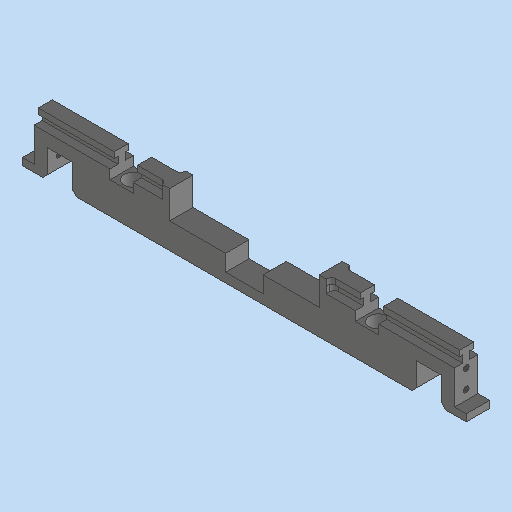
# Autodesk Inventor part: MM0937AN100_G16_152
Saved by Autodesk Inventor 2023.3 (Build 273359000, 359)
## iProperties
Created: 2024-03-13
Part Number: MM0937AN100_G16_152
Material: 1.2379 X155CrVMo12-1
Description: =<RBPARTNOTITLE2>
Document SubType Name: Modeling
Designer: FSM9BW
Mass: 187.923 g
Surface Area: 123.491 cm^2
Volume: 23.9392 cm^3
Density: 7.85 g/cm^3
Appearance: Stahl - rostfrei AnP
RBPARTMADEOF: 23 x 10 x 190 (FM)
RBDRAWINGMISSINGSPEC: --
AnP_Kategorie: 1
RBPARTNOTITLE2: Anfertigungsteil
RBSURFACE: plasma nitrided 1000 HV, Nht 0,1 + 0,1
RBPARTNOTITLE1: manufactured part
RBSURFACE2: plasmanitriert 1000 HV, Nht 0,1 + 0,1
AnP_Material: =<Material>
RBMATERIAL: =<Material>
RBMATNO: =<Part Number>
RBPARTNO: SIEHE MNR
MaxAbmaße: 23 x 10 x 190 (FM)
Author: FSM9BW
Keywords: =<RBPARTMADEOF>
Comments: =<RBSURFACE2>
Revision Number: 01
Autodesk Inventor part; units mm, degrees
ref_plane "YZ Plane" through (0, 0, 0) normal (1, 0, 0) x (0, 1, 0)
ref_plane "XZ Plane" through (0, 0, 0) normal (0, 1, 0) x (-1, 0, 0)
ref_plane "XY Plane" through (0, 0, 0) normal (0, 0, 1) x (1, 0, 0)
sketch "Skizze1" plane through (0, 0, 0) normal (0, 0, 1) x (1, 0, 0)
  line L0 (-95, -5) -> (95, -5)
  line L1 (95, -5) -> (95, 5)
  line L2 (95, 5) -> (-95, 5)
  line L3 (-95, 5) -> (-95, -5)
  line L4 (0, -7) -> (0, 7) projected
  point P0 (0, 0)
  dimension "d0" = 190
  dimension "d1" = 10
  dimension "d2" = 5
  constraints: 8 end point, 2 parallel, 1 horizontal, 1 perpendicular, 1 other
  measures "d0" distance of L1.end L2.end
  measures "d1" distance of L2.end L0.start
  measures "d2" distance from line of L2 point (0, 0)
extrude "Extrusion1" add sketch "Skizze1" along normal blind 23
sketch "Skizze2" plane through (-95, -5, 0) normal (0, -1, 0) x (1, 0, 0)
  line L0 (0, 0) -> (190, 0) projected
  line L1 (190, 0) -> (190, 23) projected
  line L2 (0, 23) -> (190, 23) projected
  line L3 (0, 0) -> (0, 23) projected
  line L4 (63, 23) -> (87, 23)
  line L5 (87, 23) -> (87, 11)
  line L6 (87, 11) -> (63, 11)
  line L7 (63, 11) -> (63, 23)
  line L8 (103, 23) -> (127, 23)
  line L9 (127, 23) -> (127, 11)
  line L10 (127, 11) -> (103, 11)
  line L11 (103, 11) -> (103, 23)
  line L12 (87, 11) -> (103, 11)
  line L13 (103, 11) -> (103, 4)
  line L14 (103, 4) -> (87, 4)
  line L15 (87, 4) -> (87, 11)
  line L16 (0, 0) -> (190, 0) projected
  point P0 (95, 0)
  point P1 (95, 0)
  point P2 (95, 0)
  point P3 (95, 0)
  dimension "d5" = 16
  dimension "d6" = 8
  dimension "d7" = 32
  dimension "d8" = 32
  dimension "d9" = 12
  dimension "d10" = 4
  constraints: 24 end point, 6 parallel, 4 point on line, 3 horizontal, 3 midpoint, 3 perpendicular
  measures "d5" distance between parallel lines of L13 L15
  measures "d6" distance from line of L15 point (95, 0)
  measures "d7" distance from line of L7 point (95, 0)
  measures "d8" distance from line of L9 point (95, 0)
  measures "d9" distance between parallel lines of L2 L6
  measures "d10" distance between parallel lines of L0 L14
extrude "Extrusion2" cut sketch "Skizze2" against normal through all contours L2 L5 L6 L7 | L9 L10 L11 L2 | L2 L11 L12 L5 | L12 L13 L14 L15
sketch "Skizze3" plane through (-95, -5, 0) normal (0, -1, 0) x (1, 0, 0)
  line L0 (63, 11) -> (63, 23) projected
  line L1 (0, 23) -> (63, 23) projected
  line L2 (0, 0) -> (0, 23) projected
  line L3 (0, 0) -> (190, 0) projected
  line L4 (190, 0) -> (190, 23) projected
  line L5 (127, 23) -> (190, 23) projected
  line L6 (127, 23) -> (127, 11) projected
  line L7 (127, 11) -> (103, 11) projected
  line L8 (103, 11) -> (103, 4) projected
  line L9 (103, 4) -> (87, 4) projected
  line L10 (87, 4) -> (87, 11) projected
  line L11 (87, 11) -> (63, 11) projected
  line L12 (0, 3) -> (5, 3)
  line L13 (5, 3) -> (5, 23)
  line L14 (5, 23) -> (0, 23)
  line L15 (0, 23) -> (0, 3)
  line L16 (190, 3) -> (185, 3)
  line L17 (185, 3) -> (185, 23)
  line L18 (185, 23) -> (190, 23)
  line L19 (190, 23) -> (190, 3)
  line L20 (0, 23) -> (63, 23) projected
  point P0 (95, 0)
  dimension "d13" = 5
  dimension "d14" = 20
  dimension "d15" = 5
  dimension "d16" = 20
  constraints: 16 end point, 4 parallel, 3 point on line, 2 horizontal, 2 perpendicular, 1 collinear
  measures "d13" distance of L14.end L13.end
  measures "d14" distance of L13.end L12.end
  measures "d15" distance of L17.end L18.end
  measures "d16" distance of L16.end L17.end
extrude "Extrusion3" cut sketch "Skizze3" against normal through all contours L13 L12 L2 L1 | L16 L17 L5 L4
sketch "Skizze4" plane through (-90, -5, 3) normal (-1, 0, 0) x (0, 0, 1)
  line L0 (0, 10) -> (20, 10) projected
  line L1 (0, 0) -> (0, 10) projected
  line L2 (20, 0) -> (0, 0) projected
  line L3 (20, 10) -> (20, 0) projected
  line L4 (20, 10) -> (20, 7.8)
  line L5 (20, 7.8) -> (17.5, 7.8)
  line L6 (17.5, 7.8) -> (17.5, 6.5)
  line L7 (17.5, 6.5) -> (14.5, 6.5)
  line L8 (14.5, 6.5) -> (14.5, 10)
  line L9 (14.5, 10) -> (20, 10)
  line L10 (20, 1.8) -> (20, 0)
  line L11 (20, 0) -> (14.5, 0)
  line L12 (14.5, 0) -> (14.5, 3.5)
  line L13 (14.5, 3.5) -> (17.5, 3.5)
  line L14 (17.5, 3.5) -> (17.5, 1.8)
  line L15 (17.5, 1.8) -> (20, 1.8)
  point P0 (-3, 5)
  dimension "d19" = 2.2
  dimension "d20" = 3.5
  dimension "d21" = 1.8
  dimension "d22" = 3.5
  dimension "d23" = 2.5
  dimension "d24" = 5.5
  constraints: 24 end point, 7 perpendicular, 4 point on line, 3 collinear, 1 horizontal, 1 vertical
  measures "d19" distance between parallel lines of L0 L5
  measures "d20" distance between parallel lines of L0 L7
  measures "d21" distance between parallel lines of L11 L15
  measures "d22" distance between parallel lines of L11 L13
  measures "d23" distance between parallel lines of L3 L6
  measures "d24" distance between parallel lines of L3 L8
extrude "Extrusion4" cut sketch "Skizze4" against normal blind 55 contours L0 L3 L5 L6 L7 L8 | L12 L13 L14 L15 L3 L2
sketch "Skizze5" plane through (90, -5, 23) normal (1, 0, 0) x (0, 0, -1)
  line L0 (0, 10) -> (20, 10) projected
  line L1 (0, 0) -> (0, 10) projected
  line L2 (20, 0) -> (0, 0) projected
  line L3 (20, 0) -> (20, 10) projected
  line L4 (0, 10) -> (5.5, 10)
  line L5 (5.5, 10) -> (5.5, 6.5)
  line L6 (5.5, 6.5) -> (2.5, 6.5)
  line L7 (2.5, 6.5) -> (2.5, 8.2)
  line L8 (2.5, 8.2) -> (0, 8.2)
  line L9 (0, 2.2) -> (0, 0)
  line L10 (0, 0) -> (5.5, 0)
  line L11 (5.5, 0) -> (5.5, 3.5)
  line L12 (5.5, 3.5) -> (2.5, 3.5)
  line L13 (2.5, 3.5) -> (2.5, 2.2)
  line L14 (2.5, 2.2) -> (0, 2.2)
  point P0 (23, 5)
  dimension "d27" = 3
  dimension "d28" = 5.5
  dimension "d29" = 3.5
  dimension "d30" = 3.5
  dimension "d31" = 1.8
  dimension "d32" = 2.2
  constraints: 22 end point, 6 perpendicular, 4 point on line, 3 collinear, 2 vertical
  measures "d27" distance between parallel lines of L5 L7
  measures "d28" distance between parallel lines of L5 L1
  measures "d29" distance of L4.end L5.end
  measures "d30" distance of L10.end L11.end
  measures "d31" distance between parallel lines of L0 L8
  measures "d32" distance between parallel lines of L2 L14
extrude "Extrusion5" cut sketch "Skizze5" against normal blind 55 contours L0 L5 L6 L7 L8 L1 | L14 L13 L12 L11 L2 L1
sketch "Skizze8" plane through (-95, -5, 0) normal (0, -1, 0) x (1, 0, 0)
  line L0 (5, 23) -> (60, 23) projected
  line L1 (5, 20.5) -> (5, 23) projected
  line L2 (5, 20.5) -> (60, 20.5) projected
  line L3 (185, 20.5) -> (130, 20.5) projected
  line L4 (185, 23) -> (185, 20.5) projected
  line L5 (130, 23) -> (185, 23) projected
  line L6 (37.5, 23) -> (47.5, 23)
  line L7 (47.5, 23) -> (47.5, 13.5)
  line L8 (47.5, 13.5) -> (37.5, 13.5)
  line L9 (37.5, 13.5) -> (37.5, 23)
  line L10 (152.5, 23) -> (142.5, 23)
  line L11 (142.5, 23) -> (142.5, 13.5)
  line L12 (142.5, 13.5) -> (152.5, 13.5)
  line L13 (152.5, 13.5) -> (152.5, 23)
  line L14 (0, 0) -> (190, 0) projected
  line L15 (130, 23) -> (130, 20.5) projected
  line L16 (60, 20.5) -> (60, 23) projected
  point P0 (95, 0)
  point P1 (42.5, 13.5)
  point P2 (95, 0)
  point P3 (147.5, 13.5)
  point P4 (95, 0)
  point P5 (142.5, 23)
  dimension "d51" = 52.5
  dimension "d52" = 52.5
  dimension "d53" = 10
  dimension "d54" = 10
  dimension "d55" = 13.5
  constraints: 16 end point, 4 midpoint, 4 parallel, 3 point on line, 2 horizontal, 2 perpendicular
  measures "d51" horizontal distance of point (42.5, 13.5) point (95, 0)
  measures "d52" horizontal distance of point (147.5, 13.5) point (95, 0)
  measures "d53" distance of L7.end L8.end
  measures "d54" distance of L11.end L12.end
  measures "d55" distance between parallel lines of L8 L14
extrude "Extrusion6" cut sketch "Skizze8" against normal through all contours L0 L7 L2 L9 | L2 L7 L8 L9 | L13 L12 L11 L3 | L3 L11 L5 L13
sketch "Skizze9" plane through (-57.5, -5, 13.5) normal (0, 0, 1) x (1, 0, 0)
  point P0 (57.5, 5)
  point P1 (5, 5)
  point P2 (110, 5)
  dimension "d58" = 52.5
  dimension "d59" = 52.5
  constraints: 2 horizontal alignment
  measures "d58" distance of point (5, 5) point (57.5, 5)
  measures "d59" distance of point (110, 5) point (57.5, 5)
hole "Bohrung3" at (-52.5, 0, 13.5) at (52.5, 0, 13.5) direction (0, 0, -1) diameter 8 end through all
sketch "Skizze10" plane through (0, 0, 0) normal (0, 0, -1) x (-1, 0, 0)
  line L0 (95, -5) -> (-95, -5) projected
  line L1 (-95, 5) -> (95, 5) projected
  line L2 (-84.25, -5) -> (-73.75, -5)
  line L3 (-73.75, -5) -> (-73.75, 5)
  line L4 (-73.75, 5) -> (-84.25, 5)
  line L5 (-84.25, 5) -> (-84.25, -5)
  line L6 (73.75, -5) -> (84.25, -5)
  line L7 (84.25, -5) -> (84.25, 5)
  line L8 (84.25, 5) -> (73.75, 5)
  line L9 (73.75, 5) -> (73.75, -5)
  point P0 (0, 0)
  point P1 (-79, -5)
  point P2 (79, -5)
  dimension "d67" = 10.5
  dimension "d68" = 10.5
  dimension "d69" = 79
  dimension "d70" = 79
  constraints: 16 end point, 4 parallel, 4 point on line, 2 horizontal, 2 midpoint, 2 perpendicular
  measures "d67" distance between parallel lines of L3 L5
  measures "d68" distance between parallel lines of L7 L9
  measures "d69" horizontal distance of point (-79, -5) point (0, 0)
  measures "d70" horizontal distance of point (79, -5) point (0, 0)
extrude "Extrusion7" cut sketch "Skizze10" against normal blind 12 contours L0 L9 L1 L7 | L0 L5 L1 L3
sketch "Skizze11" plane through (0, 0, 12) normal (0, 0, -1) x (-1, 0, 0)
  line L0 (133, 0) -> (-133, 0) projected
  line L1 (0, -7) -> (0, 7) projected
  point P0 (0, 0)
  point P1 (-79, 0)
  point P2 (79, 0)
  dimension "d73" = 79
  dimension "d74" = 79
  constraints: 2 horizontal alignment
  measures "d73" distance from line of point (-79, 0) L1
  measures "d74" distance from line of point (79, 0) L1
hole "Bohrung4" at (79, 0, 12) at (-79, 0, 12) direction (0, 0, 1) diameter 5 depth 5
sketch "Skizze12" plane through (-90, -5, 3) normal (-1, 0, 0) x (0, 0, 1)
  line L0 (0, 0) -> (0, 10) projected
  line L1 (-3, 10) -> (-3, 0) projected
  point P0 (-3, 5)
  point P1 (4, 5)
  point P2 (12, 5)
  point P3 (-3, 5)
  point P4 (-3, 5)
  dimension "d82" = 4
  dimension "d83" = 8
  constraints: 2 horizontal alignment, 2 midpoint
  measures "d82" distance from line of point (4, 5) L0
  measures "d83" distance of point (12, 5) point (4, 5)
hole "Bohrung5" at (-90, 0, 7) at (-90, 0, 15) direction (1, 0, 0) diameter 2.459 depth 8.8 tip angle 118 thread size "M3x0.5" designation "M3" class "6H" standard "ISO Metric profile"
sketch "Skizze13" plane through (90, -5, 3) normal (1, 0, 0) x (0, 0, -1)
  circle A0 centre (-4, 5) radius 1.2295 projected
  line L0 (-10.5, 0) -> (-10.5, 10) projected
  arc A1 (-12.3189, 3.8126) -> (-11.6811, 3.8126) centre (-12, 5) ccw projected
  point P0 (3, 5)
  constraints: 2 coincident
hole "Bohrung6" at (90, 0, 7) at (90, 0, 15) direction (-1, 0, 0) diameter 2.459 depth 8.8 tip angle 118 thread size "M3x0.5" designation "M3" class "6H" standard "ISO Metric profile"
fillet "Rundung1" radius 2 8 edges at (35, 3.2, 21.75) (35, 1.5, 19) (35, -2.8, 21.75) (35, -1.5, 19) (-35, 2.8, 21.75) (-35, 1.5, 19) (-35, -3.2, 21.75) (-35, -1.5, 19)
chamfer "Fase1" distance 2 angle 45 4 edges at (-73.75, 0, 0) (-84.25, 0, 0) (73.75, 0, 0) (84.25, 0, 0)
